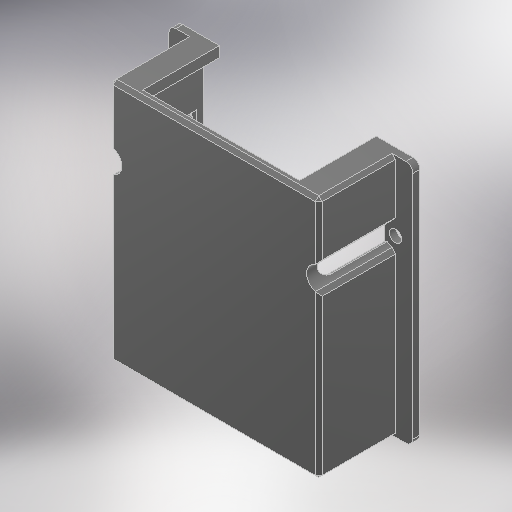
# Autodesk Inventor part: 3D_LAN-switch
Saved by Autodesk Inventor 2025.3 (Build 293356030, 356C)
## iProperties
Created: 2026-09-09
Part Number: 3D_LAN-switch
Material: 一般
Document SubType Name: Modeling
Designer: ibuki_ono
Density: 1 g/cm^3
Appearance: 滑らか - 黒
Author: ibuki_ono
## iProperties of the stored document 3D_LAN-switch_3D プリント.ipt
Created: 2026-09-09
Part Number: 3D_LAN-switch_3D プリント
Material: 一般
Document SubType Name: Modeling
Designer: ibuki_ono
Density: 1 g/cm^3
Appearance: 既定
Author: ibuki_ono
Autodesk Inventor part; units mm, degrees
ref_plane "YZ Plane" through (0, 0, 0) normal (1, 0, 0) x (0, 1, 0)
ref_plane "XZ Plane" through (0, 0, 0) normal (0, 1, 0) x (-1, 0, 0)
ref_plane "XY Plane" through (0, 0, 0) normal (0, 0, 1) x (1, 0, 0)
sketch "スケッチ1" plane through (0, 0, 0) normal (0, 0, 1) x (1, 0, 0)
  line L0 (-35, -35) -> (35, -35)
  line L1 (35, -35) -> (35, 35)
  line L2 (35, 35) -> (-35, 35)
  line L3 (-35, 35) -> (-35, -35)
  line L4 (-35, -35) -> (35, 35) construction
  line L5 (35, -35) -> (-35, 35) construction
  point P0 (0, 0)
  dimension "d0" = 70
  dimension "d1" = 70
  constraints: 12 end point, 2 midpoint, 2 parallel, 1 horizontal, 1 perpendicular
  measures "d0" distance of L2.end L1.end
  measures "d1" distance of L1.end L0.end
extrude "押し出し1" add sketch "スケッチ1" along normal blind 2
sketch "スケッチ2" plane through (0, 0, 2) normal (0, 0, 1) x (1, 0, 0)
  line L0 (35, -35) -> (35, 35) projected
  line L1 (35, 35) -> (-35, 35) projected
  line L2 (-35, 35) -> (-35, -35) projected
  line L3 (-35, -35) -> (35, -35) projected
  line L4 (-30, -35) -> (30, -35)
  line L5 (30, -35) -> (30, 35)
  line L6 (30, 35) -> (-30, 35)
  line L7 (-30, 35) -> (-30, -35)
  line L8 (-30, -35) -> (30, 35) construction
  line L9 (30, -35) -> (-30, 35) construction
  point P0 (0, 0)
  dimension "d4" = 60
  constraints: 12 end point, 2 midpoint, 2 parallel, 1 horizontal, 1 perpendicular, 1 point on line
  measures "d4" distance of L6.end L5.end
extrude "押し出し2" add sketch "スケッチ2" along normal blind 22 contours L3 L7 L1 L5
sketch "スケッチ3" plane through (0, 0, 0) normal (0, 0, -1) x (-1, 0, 0)
  line L0 (-27, -32) -> (27, -32)
  line L1 (27, -32) -> (27, 32)
  line L2 (27, 32) -> (-27, 32)
  line L3 (-27, 32) -> (-27, -32)
  line L4 (-27, -32) -> (27, 32) construction
  line L5 (27, -32) -> (-27, 32) construction
  line L6 (-35, -35) -> (-35, 35) projected
  line L7 (35, -35) -> (-35, -35) projected
  line L8 (35, 35) -> (35, -35) projected
  line L9 (-35, 35) -> (35, 35) projected
  line L10 (-30, 35) -> (30, 35) projected
  line L11 (-22.5, 32) -> (22.5, 32)
  line L12 (22.5, 32) -> (22.5, 35)
  line L13 (22.5, 35) -> (-22.5, 35)
  line L14 (-22.5, 35) -> (-22.5, 32)
  line L15 (30, -35) -> (-30, -35) projected
  line L16 (-22.5, -32) -> (22.5, -32)
  line L17 (22.5, -32) -> (22.5, -35)
  line L18 (22.5, -35) -> (-22.5, -35)
  line L19 (-22.5, -35) -> (-22.5, -32)
  point P0 (0, 0)
  point P1 (0, 32)
  point P2 (22.5, -32)
  dimension "d7" = 54
  dimension "d8" = 64
  dimension "d9" = 45
  dimension "d10" = 45
  constraints: 28 end point, 6 parallel, 5 point on line, 4 midpoint, 3 horizontal, 3 perpendicular
  measures "d7" distance of L2.end L1.end
  measures "d8" distance of L1.end L0.end
  measures "d9" distance of L13.end L12.end
  measures "d10" distance of L17.end L18.end
extrude "押し出し3" cut sketch "スケッチ3" against normal blind 22 contours L3 L2 L1 L0 | L0 L17 L7 L19 | L14 L9 L12 L2
sketch "スケッチ4" plane through (0, 0, 24) normal (0, 0, 1) x (1, 0, 0)
  line L0 (35, -35) -> (35, 35) construction
  line L1 (35, 15) -> (-35, 15) construction
  line L2 (-35, 35) -> (-35, -35) projected
  line L3 (35, -35) -> (35, 35) projected
  line L4 (30, 35) -> (-30, 35) projected
  point P0 (0, 0)
  point P1 (30, 15)
  point P2 (-30, 15)
  dimension "d30" = 30
  dimension "d31" = 30
  dimension "d32" = 20
  constraints: 4 point on line, 2 end point, 1 perpendicular
  measures "d30" horizontal distance of point (0, 0) point (30, 15)
  measures "d31" horizontal distance of point (0, 0) point (-30, 15)
  measures "d32" distance between parallel lines of L4 L1
hole "穴1" at (30, 15, 24) at (-30, 15, 24) direction (0, 0, -1) diameter 3.5 end through all counterbore diameter 7 counterbore depth 22
fillet "フィレット1" radius 4 2 edges at (27, 24.4014, 22) (-27, 24.4014, 22)
chamfer "面取り1" distance 1 angle 45 10 edges at (27, 16.8028, 10) (26.5, 15.0006, 19.9365) (27, 13.1972, 10) (-27, 13.1972, 10) (-26.5, 14.9994, 19.9365) (-27, 16.8028, 10) (30, 18.5, 13) (30, 11.5, 13) (-30, 11.5, 13) (-30, 18.5, 13)
chamfer "面取り2" distance 1 angle 45 22 edges at (0, 35, 24) (30, 35, 13) (-30, 35, 13) (-30, 27.25, 24) (-30, -12.25, 24) (-30, -35, 13) (0, -35, 24) (30, -35, 13) (30, -12.25, 24) (30, 27.25, 24) (-27, -32, 9) (-25.8284, -32, 20.8284) (-22.75, -32, 22) (-27, 32, 9) (-25.8284, 32, 20.8284) (-22.75, 32, 22) (27, 32, 9) (25.8284, 32, 20.8284) (22.75, 32, 22) (27, -32, 9) (25.8284, -32, 20.8284) (22.75, -32, 22)
fillet "フィレット2" radius 2 4 edges at (-35, 35, 1) (-35, -35, 1) (35, -35, 1) (35, 35, 1)
equation "\"d31\" = d30"
